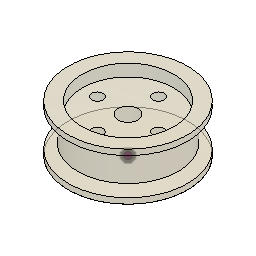
Spool (Autodesk Fusion 360 design; units mm, degrees)
Autodesk Fusion 360 part; units mm, degrees
sketch "Sketch1" plane through (0, 0, 0) normal (0, 1, 0) x (1, 0, 0)
  circle A0 centre (0, 0) radius 19.05
  dimension "d1" = 38.1
  constraint coincident A0.centre origin
  measures "d1" diameter of A0
extrude "Extrude1" add sketch "Sketch1" along normal blind 15.24
sketch "Sketch2" plane through (0, 15.24, 0) normal (0, 1, 0) x (-1, 0, 0)
  circle A0 centre (0, 0) radius 19.05
  circle A1 centre (0, 0) radius 14.605
  dimension "d4" = 29.21
  constraint coincident A0.centre A1.centre
  measures "d4" diameter of A1
extrude "Extrude2" cut sketch "Sketch2" against normal blind 3.81 contours A1
sketch "Sketch3" plane through (0, 11.43, 0) normal (0, 1, 0) x (-1, 0, 0)
  circle A0 centre (0, 0) radius 14.605
  line L0 (0, -14.605) -> (0, 14.605) construction
  line L1 (14.605, 0) -> (-14.605, 0) construction
  circle A1 centre (-9.779, 0) radius 1.8161
  circle A2 centre (0, -9.779) radius 1.8161
  circle A3 centre (0, 9.779) radius 1.8161
  circle A4 centre (9.779, 0) radius 1.8161
  circle A5 centre (0, 0) radius 3.175
  line L2 (9.779, 0) -> (-9.779, 0) construction
  line L3 (0, 9.779) -> (0, -9.779) construction
  point P0 (-14.605, 0)
  dimension "d17" = 3.6322
  dimension "d24" = 6.35
  dimension "d27" = 19.558
  dimension "d28" = 19.558
  constraint coincident A0 L0.start
  constraint coincident A0 L0.end
  constraint coincident A0 L1.start
  constraint coincident P0 L1.end
  constraint horizontal L1
  constraint equal L0 L1
  constraint perpendicular L0 L1
  constraint coincident L1 A1.centre
  constraint coincident L0 A2.centre
  constraint coincident L0 A3.centre
  constraint coincident L1 A4.centre
  constraint equal A2 A4
  constraint equal A2 A3
  constraint equal A1 A3
  constraint coincident A0.centre A5.centre
  constraint coincident A4.centre L2.start
  constraint coincident A1.centre L2.end
  constraint midpoint L2 A0.centre
  constraint coincident A3.centre L3.start
  constraint coincident A2.centre L3.end
  constraint midpoint L3 A0.centre
  measures "d17" diameter of A1
  measures "d24" diameter of A5
  measures "d27" distance of A1.centre A4.centre
  measures "d28" distance of A2.centre A3.centre
extrude "Extrude3" cut sketch "Sketch3" against normal blind 7.62 contours A1 | A2 | A3 | A4
sketch "Sketch4" plane through (0, 0, 0) normal (1, 0, 0) x (0, 0, -1)
  line L0 (-19.05, 13.462) -> (-16.002, 11.684)
  line L1 (-16.002, 11.684) -> (-16.002, 7.62)
  line L2 (-19.05, 7.62) -> (-19.05, 13.462)
  line L3 (19.05, 15.24) -> (-19.05, 15.24) construction
  line L4 (19.05, 0) -> (-19.05, 0) construction
  line L5 (-16.002, 15.24) -> (-16.002, 0) construction
  line L6 (-19.05, 7.62) -> (-16.002, 7.62)
  line L7 (-16.002, 7.62) -> (-19.05, 7.62) construction
  line L8 (-19.05, 15.24) -> (-19.05, 0) construction
  line L9 (-19.05, 7.62) -> (0, 7.62) construction
  line L10 (-19.05, 1.778) -> (-16.002, 3.556)
  line L11 (-19.05, 7.62) -> (-19.05, 1.778)
  line L12 (-19.05, 7.62) -> (-16.002, 7.62)
  line L13 (-16.002, 3.556) -> (-16.002, 7.62)
  dimension "d12" = 4.064
  dimension "d13" = 5.842
  dimension "d15" = 3.048
  constraint vertical L1
  constraint vertical L2
  constraint coincident L3 L5.start
  constraint coincident L4 L5.end
  constraint perpendicular L4 L5
  constraint midpoint L5 L1.end
  constraint perpendicular L5 L7
  constraint collinear L6 L7
  constraint coincident L3.end L8.start
  constraint coincident L4.end L8.end
  constraint collinear L2 L8
  constraint collinear L1 L5
  constraint perpendicular L8 L9
  constraint symmetric L0.start L9 L10.start
  constraint symmetric L0.end L9 L10.end
  constraint symmetric L2.start L9 L6.start
  constraint symmetric L1.end L9 L6.end
  measures "d12" distance of L0.end L1.end
  measures "d13" distance of L0.start L2.start
  measures "d15" distance of L5 L8
revolve "Revolve1" cut sketch "Sketch4" angle 360 about axis through (0, 1.75, 0) along (0, 1, 0)
extrude "Extrude4" cut sketch "Sketch3" against normal blind 39.37 contours A5
